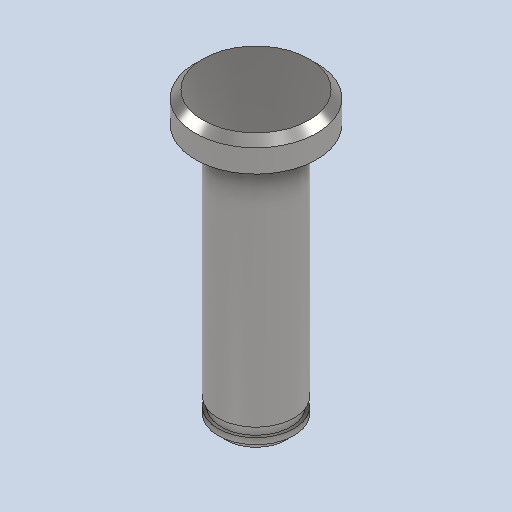
# Autodesk Inventor part: perni
Saved by Autodesk Inventor 2026.1 (Build 301233020, 233B)
## iProperties
Created: 2026-01-06
Part Number: perni
Material: Acciaio, Carbonio
Document SubType Name: Modeling
Designer: maxbu
Density: 7.85 g/cm^3
Appearance: Semilucidato
Mass: 3.35723 g
Surface Area: 4.10497 cm^2
Volume: 0.427672 cm^3
Author: maxbu
Autodesk Inventor part; units mm, degrees
ref_plane "YZ Plane" through (0, 0, 0) normal (1, 0, 0) x (0, 1, 0)
ref_plane "XZ Plane" through (0, 0, 0) normal (0, 1, 0) x (-1, 0, 0)
ref_plane "XY Plane" through (0, 0, 0) normal (0, 0, 1) x (1, 0, 0)
sketch "Schizzo1" plane through (0, 0, 0) normal (1, 0, 0) x (0, 1, 0)
  line L0 (0, 0) -> (0, -2)
  line L1 (0.5, -2.5) -> (17, -2.5)
  line L2 (17, -2.5) -> (17, -4)
  line L3 (17, -4) -> (18.5, -4)
  line L4 (19, -3.5) -> (19, 0)
  line L5 (19, 0) -> (0, 0)
  line L6 (0.9, -2.5) -> (0.9, -2.3)
  line L7 (0.9, -2.3) -> (1.5, -2.3)
  line L8 (1.5, -2.3) -> (1.5, -2.5)
  line L9 (18.5, -4) -> (19, -3.5)
  line L10 (0, -2) -> (0.5, -2.5)
  point P0 (0, -2.5)
  point P1 (19, -4)
  dimension "d0" = 17
  dimension "d1" = 2
  dimension "d2" = 2.5
  dimension "d3" = 4
  dimension "d5" = 0.6
  dimension "d6" = 15.5
  dimension "d7" = 0.5
  dimension "d8" = 0.5
  dimension "d9" = 0.5
  dimension "d10" = 0.5
  dimension "d12" = 2.3
  constraints: 22 end point, 7 perpendicular, 6 point on line, 2 vertical
  measures "d0" distance of point (0, -2.5) L1.end
  measures "d1" distance of L2.end point (19, -4)
  measures "d2" distance between parallel lines of L5 L1
  measures "d3" distance between parallel lines of L5 L3
  measures "d5" distance between parallel lines of L6 L8
  measures "d6" distance between parallel lines of L2 L8
  measures "d7" distance of L3.end point (19, -4)
  measures "d8" distance of L4.start point (19, -4)
  measures "d9" distance of L0.end point (0, -2.5)
  measures "d10" distance of L1.start point (0, -2.5)
  measures "d12" distance between parallel lines of L5 L7
revolve "Rivoluzione1" add sketch "Schizzo1" angle 360 about axis through (0, 19, 0) along (0, -1, 0) contours L5 L4 L9 L3 L2 L1 L8 L7 L6 L10 L0
equation "\"d8\" = d7"
equation "\"d9\" = d7"
equation "\"d10\" = d9"
